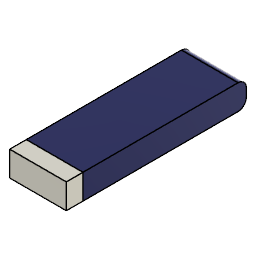
MonoJavlin (Autodesk Fusion 360 archive; units mm, degrees)
design "Turnigy 3S 1500mAh 11.1V 40C"
part number: 2026-10-26-09-45-28-599
Autodesk Fusion 360 part; units mm, degrees
sketch "Sketch1" plane through (0, 0, 0) normal (0, 0, 1) x (1, 0, 0)
  line L0 (0, 0) -> (34, 0)
  line L1 (34, 0) -> (34, 108)
  line L2 (34, 108) -> (0, 108)
  line L3 (0, 108) -> (0, 0)
  dimension "d1" = 34
  dimension "d2" = 108
  constraint horizontal L0
  constraint vertical L1
  constraint horizontal L2
  constraint vertical L3
  constraint coincident L0.start L3.end
  measures "d1" distance of L0.start L0.end
  measures "d2" distance of L0.start L2.end
extrude "Extrude1" add sketch "Sketch1" along normal blind 15 makes body 1
fillet "Fillet1" radius 5 2 edges at (17, 108, 15) (17, 108, 0) on bodies 1
split "Split1" by plane through (17, 10, 7.5) normal (0, -1, 0) bodies 1 makes body 2 at (11.3333, 0, 5)
shell "Shell1" thickness 5.5 removed faces 1 at (11.3333, 10, 10) on bodies 1
